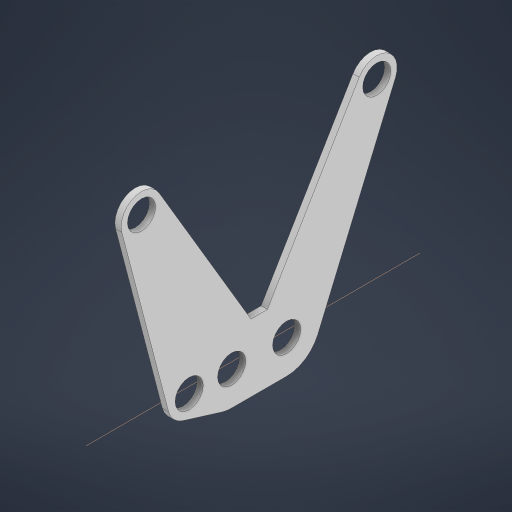
# Autodesk Inventor part: DTraining2_001_E2Base
Saved by Autodesk Inventor 2024.4 (Build 284460000, 460)
## iProperties
Created: 2026-06-14
Part Number: DTraining2_001_E2Base
Material: Generic
Document SubType Name: Modeling
Designer: hs4ho
Density: 1 g/cm^3
Appearance: Default
Author: hs4ho
Autodesk Inventor part; units mm, degrees
ref_plane "YZ Plane" through (0, 0, 0) normal (1, 0, 0) x (0, 1, 0)
ref_plane "XZ Plane" through (0, 0, 0) normal (0, 1, 0) x (-1, 0, 0)
ref_plane "XY Plane" through (0, 0, 0) normal (0, 0, 1) x (1, 0, 0)
sketch "Sketch1" plane through (0, 0, 0) normal (1, 0, 0) x (0, 1, 0)
  circle A0 centre (0, 0) radius 15.24 construction
  circle A1 centre (0, -43.18) radius 27.94 construction
  circle A2 centre (0, -99.06) radius 27.94 construction
  line L0 (0, -277.0805) -> (0, 133.9641) projected
  circle A3 centre (0, -43.18) radius 14.2875
  circle A4 centre (0, -99.06) radius 14.2875
  circle A5 centre (0, 0) radius 14.2875
  line L1 (0, -71.12) -> (181.3994, -71.12) construction
  line L2 (181.3994, -71.12) -> (181.3994, -139.827) construction
  line L3 (181.3994, -71.12) -> (181.3994, -2.413) construction
  line L4 (181.3994, -2.413) -> (181.3994, 48.387) construction
  line L5 (181.3994, -139.827) -> (181.3994, -190.627) construction
  circle A6 centre (181.3994, 48.387) radius 14.2875
  circle A7 centre (181.3994, -190.627) radius 14.2875
  circle A8 centre (181.3994, 48.387) radius 14.3256 construction
  circle A9 centre (181.3994, -190.627) radius 14.3256 construction
  line L6 (177.7747, 62.2465) -> (-3.8561, 14.7441) construction
  line L7 (-27.94, -43.18) -> (-27.94, -99.06) construction
  line L8 (188.6972, 36.0596) -> (27.94, -59.1085) construction
  line L9 (27.94, -59.1085) -> (27.94, -83.1315) construction
  line L10 (27.94, -83.1315) -> (188.6972, -178.2996) construction
  line L11 (175.8152, -203.8194) -> (-10.891, -124.7899) construction
  line L12 (-14.5659, 4.4824) -> (-26.7042, -34.9624) construction
  arc A10 (-3.8561, 14.7441) -> (-14.5659, 4.4824) centre (0, 0) ccw construction
  arc A11 (188.6972, 36.0596) -> (177.7747, 62.2465) centre (181.3994, 48.387) ccw construction
  arc A12 (175.8152, -203.8194) -> (188.6972, -178.2996) centre (181.3994, -190.627) ccw construction
  arc A13 (-27.94, -99.06) -> (-10.891, -124.7899) centre (0, -99.06) ccw construction
  arc A14 (-26.7042, -34.9624) -> (-27.94, -43.18) centre (0, -43.18) ccw construction
  line L13 (-5.4628, 20.8875) -> (176.168, 68.3898)
  arc A15 (191.932, 30.5953) -> (176.168, 68.3898) centre (181.3994, 48.387) ccw
  line L14 (191.932, 30.5953) -> (34.29, -62.7286)
  line L15 (34.29, -62.7286) -> (34.29, -79.5114)
  line L16 (34.29, -79.5114) -> (191.932, -172.8353)
  arc A16 (173.34, -209.6671) -> (191.932, -172.8353) centre (181.3994, -190.627) ccw
  line L17 (173.34, -209.6671) -> (-13.3663, -130.6376)
  arc A17 (-34.29, -99.06) -> (-13.3663, -130.6376) centre (0, -99.06) ccw
  line L18 (-34.29, -99.06) -> (-34.29, -43.18)
  arc A18 (-32.7733, -33.0947) -> (-34.29, -43.18) centre (0, -43.18) ccw
  line L19 (-32.7733, -33.0947) -> (-20.6351, 6.35)
  arc A19 (-5.4628, 20.8875) -> (-20.6351, 6.35) centre (0, 0) ccw
  dimension "d0" = 30.48
  dimension "d1" = 55.88
  dimension "d3" = 28.575
  dimension "d13" = 28.575
  dimension "d14" = 28.575
  dimension "d15" = 68.707
  dimension "d16" = 68.707
  dimension "d17" = 50.8
  dimension "d18" = 50.8
  dimension "d19" = 203.2
  dimension "d20" = 28.575
  dimension "d21" = 28.575
  dimension "d22" = 28.6512
  dimension "d23" = 28.6512
  dimension "d24" = 6.35
  constraints: 38 end point, 31 point on circle, 20 centre point, 19 tangent, 7 coincident, 5 concentric, 5 vertical, 4 point on line, 1 equal radius, 1 perpendicular, 11 other
  measures "d0" diameter of A0
  measures "d1" diameter of A1
  measures "d3" diameter of A3
  measures "d13" diameter of A4
  measures "d14" diameter of A5
  measures "d15" distance of L1.end L2.end
  measures "d16" distance of L1.end L3.end
  measures "d17" distance of L3.end L4.end
  measures "d18" distance of L2.end L5.end
  measures "d19" distance of A1.centre L4.end
  measures "d20" diameter of A6
  measures "d21" diameter of A7
  measures "d22" diameter of A8
  measures "d23" diameter of A9
  measures "d24" distance between parallel lines of L6 L13
extrude "Extrusion2" add sketch "Sketch1" along normal blind 6.35 contours L17 A17 L18 A18 L19 A19 L13 L0 A5 A3 A4 | L0 A4 A3 A5 L13 A15 L14 L15 L16 A16 L17
body "Solid2"
